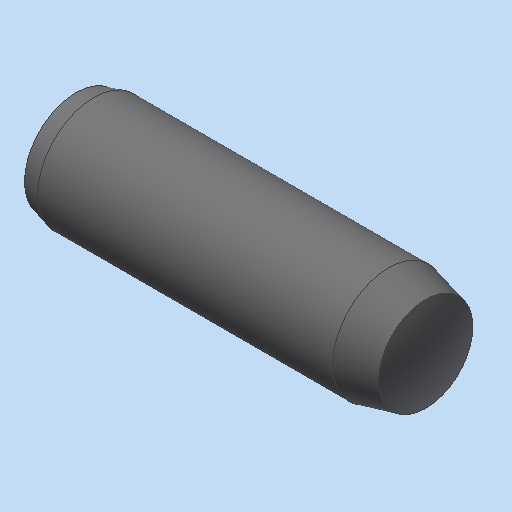
# Autodesk Inventor part: Zylinderstift_DIN_7979D_5_x_16
Saved by Autodesk Inventor 2023.3 (Build 273359000, 359)
## iProperties
Part Number: Zylinderstift_DIN_7979D_5_x_16
Document SubType Name: Standard Catalog Part
Created: 2005-12-08
Material: xStahl_AnP_Dummymaterial
Description: =<RBPARTNOTITLE2>
Vendor: NORM8
Designer: bum9ba
Manufacturer: Standard
Standards Organization: Custom
Density: 7.85 g/cm^3
Appearance: Stahl - normal AnP
Mass: 2.00352 g
Surface Area: 3.46028 cm^2
Volume: 0.255226 cm^3
Control State: 0
Master: False
Checked Out: False
Shininess: 64.0
Length Units: 11269
Angle Units: 11279
Time Units: 11290
Mass Units: 11283
Length Display Precision: 3
Angle Display Precision: 2
Compacted: True
Ausgabe: 00
Blattnr: 000
Fläche: 0,000 mm^2
Masse: 0,000 kg
Volumen: 0,000 mm^3
CNS_NB: Zylinderstift DIN 7979D 5 x 16
CNS_NN: DIN 7979-D
CNS_NT: Zylinderstift, mit Innengewinde, gehaertet
CNS_NBSYN: Zylinderstift DIN 7979D $NENN.
CNS_LINA: Zylinderstift DIN 7979D 5 x 16
CNS_NENN: 5 x 16
CNS_D: 5.000
CNS_D1: 3.000
CNS_D2: 2.242
CNS_DA: 3.300
CNS_P: 0.500
CNS_L: 16.000
CNS_B: 6.000
CNS_T1: 1.000
CNS_T2: 10.000
CNS_A1: 0.600
CNS_A2: 0.800
CNS_F: 2.100
CNS_KT: X
CNS_LINA2: Zylinderstift DIN 7979D 5 x 16
PSOL_IDENT_0: {\\ba0cad02\tef2_cad\_bibliothek\23d-libs\norm\din_en_iso\stifte\scherstifte\din_7979_d.prj},205 {M=
PSOL_IDENT_1: Nenngewinde},{VTYP=3D},{NB=Zylinderstift DIN 7979D 5 x 16},{LINA=Zylinderstift DIN 7979D 5 x 16},{NN
PSOL_IDENT_2: =DIN 7979-D},{DATE=8.12.2005},{GEOMDATE=26.11.2003},{VERSION=v1},{LINEID=10},{LINESUBID=-1},{WBVAR=}
PSOL_IDENT_3: {NB=Zylinderstift DIN 7979D 5 x 16},{LINA=Zylinderstift DIN 7979D 5 x 16},{KT=X},{IDNR=},{NENN=5 x
PSOL_IDENT_4: 16},{D=5.000},{D1=3.000},{D2=2.242},{DA=3.300},{P=0.500},{L=16.000},{B=6.000},{T1=1.000},{T2=10.000
PSOL_IDENT_5: },{A1=0.600},{A2=0.800},{F=2.100}
RBDRAWINGMISSINGSPEC: --
RBPARTNOTITLE2: Zylinderstift mit Innengewinde, gehaertet
RBPARTNOTITLE1: Parallel pins with internal thread, hardened
AnP_Kategorie: 5
RBPARTMADEOF: DIN 7979 D - 5 x 16
Density: 0.0
Volumn: 0.0
Area: 0.0
PropertySet Name: Model Information
Author: bum9ba
Keywords: =<RBPARTMADEOF>
Comments: =<RBSURFACE2>
Revision Number: 01
Autodesk Inventor part; units mm, degrees
sketch "Skizze_4" plane through (0, 0, 0) normal (0, 1, 0) x (-1, 0, 0)
  line L0 (-16, 0) -> (0, 0)
  line L1 (-10.6472, 0) -> (-10, -1.121)
  line L2 (-10, -1.121) -> (-1.9163, -1.121)
  line L3 (-1.9163, -1.121) -> (-1, -1.65)
  line L4 (-1, -1.65) -> (0, -1.65)
  line L5 (0, -1.65) -> (0, -2.2856)
  line L6 (0, -2.2856) -> (-0.8, -2.5)
  line L7 (-0.8, -2.5) -> (-13.9, -2.5)
  line L8 (-13.9, -2.5) -> (-15.5385, -2.0981)
  arc A0 (-16, 0) -> (-15.5385, -2.0981) centre (-11, 0) ccw
  line L9 (-16, 0) -> (-10.6472, 0)
  constraints: 20 end point, 2 point on circle, 1 centre point
revolve "Drehung1" add sketch "Skizze_4" angle 360 about axis through (16, 0, 0) along (1, 0, 0)
thread "Gewinde1" size "M3x0.5" class "6H" standard "ISO Metric profile" length 8.0837
ref_plane "IP2_XY" through (0, 0, 0) normal (1, 0, 0) x (0, 0, -1)
ref_plane "IP2_YZ" through (0, 0, 0) normal (0, 0, -1) x (0, 1, 0)
ref_plane "IP2_ZX" through (0, 0, 0) normal (0, 1, 0) x (1, 0, 0)
ref_plane "IP1_XY" through (8, 0, 0) normal (1, 0, 0) x (0, 0, -1)
ref_plane "IP1_YZ" through (8, 0, 0) normal (0, 0, -1) x (0, 1, 0)
ref_plane "IP1_ZX" through (8, 0, 0) normal (0, 1, 0) x (1, 0, 0)
ref_plane "IP3_XY" through (16, 0, 0) normal (1, 0, 0) x (0, 0, -1)
ref_plane "IP3_YZ" through (16, 0, 0) normal (0, 0, -1) x (0, 1, 0)
ref_plane "IP3_ZX" through (16, 0, 0) normal (0, 1, 0) x (1, 0, 0)
